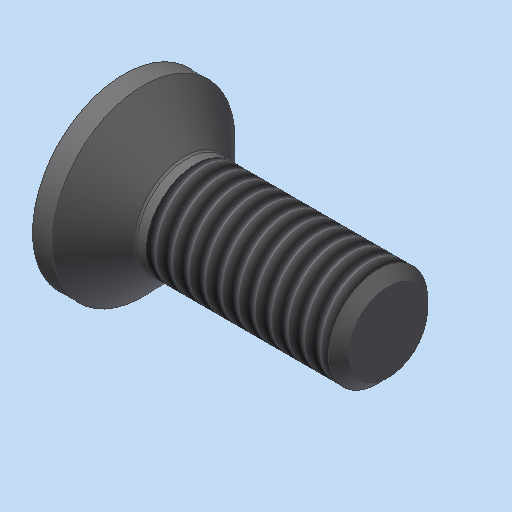
# Autodesk Inventor part: Senkschraube_ISO_10642___M3x8
Saved by Autodesk Inventor 2023.3 (Build 273359000, 359)
## iProperties
Shininess: 64.0
Length Units: 11269
Angle Units: 11279
Time Units: 11290
Mass Units: 11283
Length Display Precision: 3
Angle Display Precision: 2
Compacted: True
Part Number: Senkschraube_ISO_10642___M3x8
Document SubType Name: Modeling
Created: 2004-03-30
Material: xStahl_AnP_Dummymaterial
Description: =<RBPARTNOTITLE2>
Vendor: NORM8
Designer: S.Riedelsheimer
Manufacturer: Standard
Standards Organization: Custom
Density: 7.85 g/cm^3
Mass: 0.566087 g
Surface Area: 1.29008 cm^2
Volume: 0.072113 cm^3
Appearance: Stahl - normal AnP
DOC_ID: 5 F45 Senkschraube_ISO_10642___M3x8
Control State: 0
Master: False
Checked Out: False
CNS_NB: Senkschraube ISO 10642 - M3x8
CNS_NN: ISO 10642
CNS_NT: Senkschrauben mit Innensechskant
CNS_NBSYN: Senkschraube $NENN.
CNS_LINA: Senkschraube ISO 10642 - M3x8
CNS_D: 3.000
CNS_D3: 2.387
CNS_P: 0.500
CNS_L: 8.000
CNS_S: 2.000
CNS_DK: 5.540
CNS_K: 1.860
CNS_T: 1.100
CNS_R: 0.100
CNS_LS: 0.000
CNS_LG: 0.000
CNS_NENN: ISO 10642 - M3x8
CNS_YW: 1.571
CNS_YC: 0.590
CNS_KT: DUMMY
PSOL_IDENT_0: {C:\partsolutions8\data\23d-libs\bosch_bamberg\schrauben\senkschrauben\iso_10642.prj},166 {M=Nenngew
PSOL_IDENT_1: inde},{VTYP=3D},{NB=Senkschraube ISO 10642 - M3x8},{NN=ISO 10642},{DATE=26.11.2003},{GEOMDATE=26.11.
PSOL_IDENT_2: 2003},{VERSION=v1},{LINEID=10},{LINESUBID=-1},{WBVAR=}  {NB=Senkschraube ISO 10642 - M3x8},{LINA=Sen
PSOL_IDENT_3: kschraube ISO 10642 - M3x8},{KT=DUMMY},{IDNR=},{D=3.000},{D3=2.387},{P=0.500},{L=8.000},{S=2.000},{D
PSOL_IDENT_4: K=5.540},{K=1.860},{T=1.100},{R=0.100},{LS=0.000},{LG=0.000},{NENN=ISO 10642 - M3x8},{YW=1.57079},{Y
PSOL_IDENT_5: C=0.589992}
DEF_STKID: T19352
Bezeichnung1: Senkschraube ISO 10642 - M3x8
Bezeichnung2: Senkschrauben mit Innensechskant
RBPARTNOTITLE2: Senkschrauben mit Innensechskant
RBPARTMADEOF: ISO 10642 - M3x8
RBPARTNOTITLE1: Hexagon socket countersunk head screws
RBDRAWINGMISSINGSPEC: --
AnP_Kategorie: 4
Density: 0.0
Volumn: 0.0
Area: 0.0
PropertySet Name: Model Information
Title: Senkschraube ISO 10642 - M3x8
Author: S.Riedelsheimer
Keywords: =<RBPARTMADEOF>
Comments: =<RBSURFACE2>
Revision Number: 01
Autodesk Inventor part; units mm, degrees
sketch "Sketch_1" plane through (0, 0, 0) normal (0, 0, 1) x (1, 0, 0)
  line L0 (0.3094, 0) -> (8, 0)
  line L1 (8, 0) -> (8, -1.1935)
  line L2 (8, -1.1935) -> (7.6935, -1.5)
  line L3 (7.6935, -1.5) -> (1.9014, -1.5)
  arc A0 (1.9014, -1.5) -> (1.8307, -1.5293) centre (1.9014, -1.6) ccw
  line L4 (1.8307, -1.5293) -> (0.59, -2.77)
  line L5 (0.59, -2.77) -> (0, -2.77)
  line L6 (0, -2.77) -> (0, -1.1547)
  line L7 (0, -1.1547) -> (0.3094, 0)
  line L8 (0.3094, 0) -> (8, 0)
  constraints: 18 end point, 2 point on circle, 1 centre point
revolve "Drehung1" add sketch "Sketch_1" angle 360 about axis through (0.3094, 0, 0) along (1, 0, 0)
thread "Gewinde1" size "M3x0.5" class "6g" standard "ANSI Metric M Profile" length 5.527
sketch "Sketch_3" plane through (0, 0, 0) normal (1, 0, 0) x (0, 1, 0)
  line L0 (0, 1.1547) -> (-1, 0.5774)
  line L1 (-1, 0.5774) -> (-1, -0.5774)
  line L2 (-1, -0.5774) -> (0, -1.1547)
  line L3 (0, -1.1547) -> (1, -0.5774)
  line L4 (1, -0.5774) -> (1, 0.5774)
  line L5 (1, 0.5774) -> (0, 1.1547)
  constraints: 12 end point
extrude "Extrusion1" cut sketch "Sketch_3" along normal blind 1.1
ref_plane "IP1_XY" through (0, 0, 0) normal (1, 0, 0) x (0, 0, -1)
ref_plane "IP1_YZ" through (0, 0, 0) normal (0, 0, -1) x (0, 1, 0)
ref_plane "IP2_XY" through (8, 0, 0) normal (1, 0, 0) x (0, 0, -1)
ref_plane "IP2_YZ" through (8, 0, 0) normal (0, 0, -1) x (0, 1, 0)
